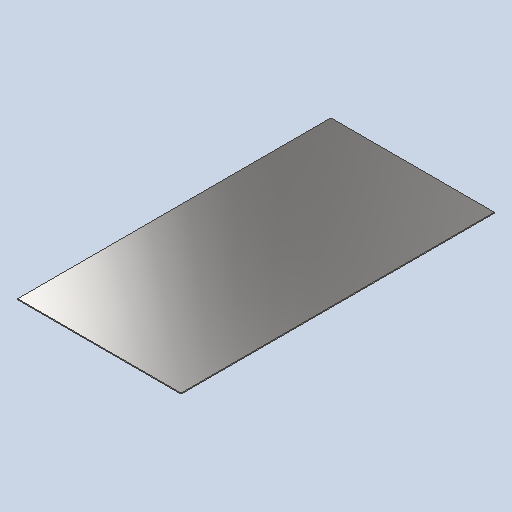
# Autodesk Inventor part: RDS-1202 Bunker Front Wall
Saved by Autodesk Inventor 2026.2 (Build 302298000, 298)
## iProperties
Created: 2026-10-18
Part Number: RDS-1202 Bunker Front Wall
Material: Stainless Steel, Austenitic
Description: Bunker front wall (tray side), AISI 304 2 mm
Document SubType Name: Sheet Metal
Designer: admin
Stock Number: Бункер — передняя стенка
Density: 8 g/cm^3
Flat Pattern Width: 69 cm
Flat Pattern Length: 36 cm
Flat Pattern Area: 2484 cm^2
Sheet Metal Rule: Default
Sheet Metal Width: 690,000 mm
Sheet Metal Length: 360,000 mm
Sheet Metal Area: 248400,000 mm^2
Appearance: Semi-Polished
Author: admin
Autodesk Inventor part; units mm, degrees
ref_plane "YZ Plane" through (0, 0, 0) normal (1, 0, 0) x (0, 1, 0)
ref_plane "XZ Plane" through (0, 0, 0) normal (0, 1, 0) x (-1, 0, 0)
ref_plane "XY Plane" through (0, 0, 0) normal (0, 0, 1) x (1, 0, 0)
sketch "Sketch1" plane through (0, 0, 0) normal (0, 1, 0) x (-1, 0, 0)
  line L0 (158, -200) -> (-202, -200)
  line L1 (-202, -200) -> (-202, 490)
  line L2 (-202, 490) -> (158, 490)
  line L3 (158, 490) -> (158, -200)
  dimension "d0" = 360
  dimension "d1" = 690
  measures "d0" distance of L0.start L0.end
  measures "d1" distance of L0.end L1.end
extrude "Plate1" add sketch "Sketch1" along normal blind 2
equation "\"d0\" = Front1202_Width"
equation "\"d1\" = Front1202_Height"
equation "\"d2\" = Thickness"
equation "\"BendRadius\" = Thickness"
equation "\"BendReliefWidth\" = Thickness"
equation "\"BendReliefDepth\" = 0.5 * Thickness"
equation "\"CornerReliefSize\" = 4 * Thickness"
equation "\"MinimumRemnant\" = 2 * Thickness"
equation "\"TransitionRadius\" = BendRadius"
equation "\"JacobiRadiusSize\" = BendRadius"
equation "\"GapSize\" = Thickness"
equation "\"Front1202_Width\" = 360"
equation "\"Front1202_Height\" = 690"
equation "\"Thickness\" = 2"
body "Solid1"
